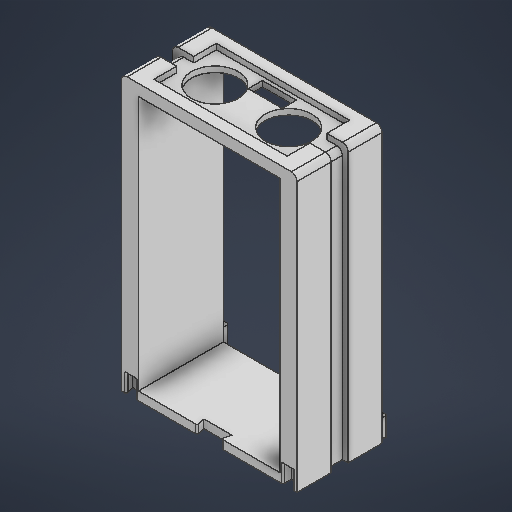
# Autodesk Inventor part: Car Sensor Gate
Saved by Autodesk Inventor 2026.4 (Build 304435000, 435)
## iProperties
Created: 2026-10-05
Part Number: Car Sensor Gate
Material: Generic
Document SubType Name: Modeling
Designer: LENOVO
Density: 1 g/cm^3
Appearance: Default
Author: LENOVO
Autodesk Inventor part; units mm, degrees
ref_plane "YZ Plane" through (0, 0, 0) normal (1, 0, 0) x (0, 1, 0)
ref_plane "XZ Plane" through (0, 0, 0) normal (0, 1, 0) x (-1, 0, 0)
ref_plane "XY Plane" through (0, 0, 0) normal (0, 0, 1) x (1, 0, 0)
sketch "Sketch1" plane through (0, 0, 0) normal (0, 1, 0) x (-1, 0, 0)
  line L0 (-25, 15) -> (25, 15)
  line L1 (25, 15) -> (25, -15)
  line L2 (25, -15) -> (-25, -15)
  line L3 (-25, -15) -> (-25, 15)
  line L4 (-25, 15) -> (25, -15) construction
  line L5 (25, 15) -> (-25, -15) construction
  point P0 (0, 0)
  dimension "d0" = 50
  dimension "d1" = 30
  constraints: 12 end point, 2 midpoint, 2 parallel, 1 horizontal, 1 perpendicular
  measures "d0" distance of L1.end L2.end
  measures "d1" distance of L0.end L1.end
extrude "Extrusion1" add sketch "Sketch1" along normal blind 2
sketch "Sketch2" plane through (0, 0, 0) normal (0, -1, 0) x (1, 0, 0)
  line L0 (25, 15) -> (25, -15) projected
  line L1 (25, 15) -> (31, 15)
  line L2 (31, 15) -> (31, -15)
  line L3 (31, -15) -> (25, -15)
  line L4 (25, -15) -> (25, 15)
  point P0 (0, 0)
  dimension "d4" = 6
  constraints: 8 end point, 2 parallel, 1 horizontal, 1 perpendicular
  measures "d4" distance of L2.end L3.end
extrude "Extrusion2" add sketch "Sketch2" against normal blind 6
mirror "Mirror1" about plane through (0, 0, 0) normal (1, 0, 0) of "Extrusion2"
sketch "Sketch3" plane through (0, 0, 0) normal (0, -1, 0) x (1, 0, 0)
  line L0 (-31, -15) -> (31, -15)
  line L1 (25, -15) -> (-25, -15)
  line L2 (-5, -12) -> (-5, -18)
  line L3 (-5, -18) -> (5, -18)
  line L4 (5, -18) -> (5, -12)
  line L5 (5, -12) -> (-5, -12)
  line L6 (-5, -12) -> (5, -18) construction
  line L7 (-5, -18) -> (5, -12) construction
  line L8 (-31, -15) -> (-25, -15)
  line L9 (-30, -12) -> (-30, -18)
  line L10 (-30, -18) -> (-26, -18)
  line L11 (-26, -18) -> (-26, -12)
  line L12 (-26, -12) -> (-30, -12)
  line L13 (-30, -12) -> (-26, -18) construction
  line L14 (-30, -18) -> (-26, -12) construction
  line L15 (-5, -18) -> (-4.1962, -15)
  line L16 (-5, -18) -> (-5, -14.8942) construction
  line L17 (5, -18) -> (4.1962, -15)
  line L18 (-30, -18) -> (-29.1962, -15)
  line L19 (-31, -15) -> (31, -15)
  line L20 (-30, -18) -> (-30, -14.8942) construction
  line L21 (26, -18) -> (26, -12)
  line L22 (30, -12) -> (30, -18)
  line L23 (30, -18) -> (26, -18)
  line L24 (26, -12) -> (30, -12)
  line L25 (30, -12) -> (26, -18) construction
  line L26 (30, -18) -> (29.1962, -15)
  line L27 (30, -18) -> (30, -14.8942) construction
  line L28 (31, -15) -> (25, -15)
  line L29 (30, -18) -> (26, -12) construction
  line L30 (31, -15) -> (-31, -15) projected
  line L31 (31, -15) -> (31, 15) projected
  line L32 (-31, 15) -> (31, 15) projected
  line L33 (-31, -15) -> (-31, 15) projected
  line L34 (-31, 0) -> (31, 0)
  line L35 (-31, 15) -> (31, 15)
  line L36 (25, 15) -> (-25, 15)
  line L37 (-5, 12) -> (-5, 18)
  line L38 (-5, 18) -> (5, 18)
  line L39 (5, 18) -> (5, 12)
  line L40 (5, 12) -> (-5, 12)
  line L41 (-5, 12) -> (5, 18) construction
  line L42 (-5, 18) -> (5, 12) construction
  line L43 (-31, 15) -> (-25, 15)
  line L44 (-30, 12) -> (-30, 18)
  line L45 (-30, 18) -> (-26, 18)
  line L46 (-26, 18) -> (-26, 12)
  line L47 (-26, 12) -> (-30, 12)
  line L48 (-30, 12) -> (-26, 18) construction
  line L49 (-30, 18) -> (-26, 12) construction
  line L50 (-5, 18) -> (-4.1962, 15)
  line L51 (-5, 18) -> (-5, 14.8942) construction
  line L52 (5, 18) -> (4.1962, 15)
  line L53 (-30, 18) -> (-29.1962, 15)
  line L54 (-31, 15) -> (31, 15)
  line L55 (-30, 18) -> (-30, 14.8942) construction
  line L56 (26, 18) -> (26, 12)
  line L57 (30, 12) -> (30, 18)
  line L58 (30, 18) -> (26, 18)
  line L59 (26, 12) -> (30, 12)
  line L60 (30, 12) -> (26, 18) construction
  line L61 (30, 18) -> (29.1962, 15)
  line L62 (30, 18) -> (30, 14.8942) construction
  line L63 (31, 15) -> (25, 15)
  line L64 (30, 18) -> (26, 12) construction
  line L65 (31, 15) -> (-31, 15)
  line L66 (-26, 12) -> (-26, 18)
  line L67 (-30, 18) -> (-30, 12)
  line L68 (-30, 18) -> (-26, 12) construction
  line L69 (-30, 12) -> (-26, 18) construction
  line L70 (-30, 12) -> (-30, 15.1058) construction
  line L71 (-30, 12) -> (-29.1962, 15)
  line L72 (-30, 12) -> (-26, 12)
  line L73 (5, 12) -> (5, 18)
  line L74 (5, 12) -> (4.1962, 15)
  line L75 (26, 12) -> (26, 18)
  line L76 (30, 12) -> (26, 12)
  line L77 (30, 12) -> (29.1962, 15)
  line L78 (30, 12) -> (26, 18) construction
  line L79 (30, 12) -> (30, 15.1058) construction
  line L80 (30, 18) -> (30, 12)
  line L81 (30, 18) -> (26, 12) construction
  line L82 (-5, 18) -> (-5, 12)
  line L83 (-5, 12) -> (-5, 15.1058) construction
  line L84 (-5, 12) -> (-4.1962, 15)
  line L85 (-5, 12) -> (5, 18) construction
  line L86 (-5, 18) -> (5, 12) construction
  line L87 (-5, 12) -> (5, 12)
  point P0 (0, 0)
  point P1 (-28, -15)
  point P2 (28, -15)
  point P3 (-131.328, -107.9645)
  point P4 (-131.328, -104.7683)
  point P5 (-131.328, -82.9645)
  point P6 (-131.328, -74.5722)
  point P7 (-131.328, -52.7683)
  point P8 (-131.328, -49.5722)
  point P9 (-28, 15)
  point P10 (28, 15)
  point P11 (26, -15)
  point P12 (-26, -15)
  dimension "d7" = 6
  dimension "d8" = 10
  dimension "d9" = 6
  dimension "d10" = 4
  dimension "d11" = 15
  dimension "d12" = 15
  constraints: 168 end point, 42 symmetric about line, 5 midpoint, 4 parallel, 4 point on line, 2 equal length, 2 perpendicular, 1 collinear
  measures "d7" distance of L4.end L3.end
  measures "d8" distance of L3.end L2.end
  measures "d9" distance of L11.end L10.end
  measures "d10" distance of L10.end L9.end
  measures "d11" angle of L15 L16
  measures "d12" angle of L18 L20
extrude "Extrusion3" add sketch "Sketch3" against normal blind 2 contours L0 L17 L3 L15 | L11 L10 L18 L0 | L0 L26 L23 L21
sketch "Sketch5" plane through (0, 0, 0) normal (0, -1, 0) x (1, 0, 0)
  line L0 (31, -15) -> (29.1962, -15) projected
  line L1 (31, -15) -> (31, 15) projected
  line L2 (-31, 15) -> (31, 15) projected
  line L3 (-31, -15) -> (-31, 15) projected
  line L4 (-29.1962, -15) -> (-31, -15) projected
  line L5 (-29.1962, -15) -> (-30, -18) projected
  line L6 (-30, -18) -> (-26, -18) projected
  line L7 (-26, -18) -> (-26, -15) projected
  line L8 (-4.1962, -15) -> (-26, -15) projected
  line L9 (-4.1962, -15) -> (-5, -18) projected
  line L10 (-5, -18) -> (5, -18) projected
  line L11 (5, -18) -> (4.1962, -15) projected
  line L12 (26, -15) -> (4.1962, -15) projected
  line L13 (26, -15) -> (26, -18) projected
  line L14 (26, -18) -> (30, -18) projected
  line L15 (30, -18) -> (29.1962, -15) projected
  line L16 (31, -15) -> (-31, -15)
  line L17 (-26, -15) -> (-29.1962, -15) projected
  line L18 (31, 0) -> (-31, 0)
  line L19 (-29.1962, -15) -> (-30, -12)
  line L20 (-30, -12) -> (-26, -12)
  line L21 (-26, -12) -> (-26, -15)
  line L22 (-4.1962, -15) -> (-5, -12)
  line L23 (-5, -12) -> (5, -12)
  line L24 (5, -12) -> (4.1962, -15)
  line L25 (26, -15) -> (26, -12)
  line L26 (26, -12) -> (30, -12)
  line L27 (30, -12) -> (29.1962, -15)
  line L28 (31, 15) -> (29.1962, 15)
  line L29 (31, 15) -> (31, -15)
  line L30 (-31, 15) -> (-31, -15)
  line L31 (-29.1962, 15) -> (-31, 15)
  line L32 (-29.1962, 15) -> (-30, 18)
  line L33 (-30, 18) -> (-26, 18)
  line L34 (-26, 18) -> (-26, 15)
  line L35 (-4.1962, 15) -> (-26, 15)
  line L36 (-4.1962, 15) -> (-5, 18)
  line L37 (-5, 18) -> (5, 18)
  line L38 (5, 18) -> (4.1962, 15)
  line L39 (26, 15) -> (4.1962, 15)
  line L40 (26, 15) -> (26, 18)
  line L41 (26, 18) -> (30, 18)
  line L42 (30, 18) -> (29.1962, 15)
  line L43 (31, 15) -> (-31, 15)
  line L44 (-26, 15) -> (-29.1962, 15)
  line L45 (-4.1962, 15) -> (-5, 12)
  line L46 (-26, 12) -> (-26, 15)
  line L47 (-29.1962, 15) -> (-30, 12)
  line L48 (-30, 12) -> (-26, 12)
  line L49 (-5, 12) -> (5, 12)
  line L50 (26, 15) -> (26, 12)
  line L51 (30, 12) -> (29.1962, 15)
  line L52 (26, 12) -> (30, 12)
  line L53 (5, 12) -> (4.1962, 15)
  point P0 (0, 0)
  constraints: 74 end point, 28 symmetric about line, 2 midpoint, 1 collinear
extrude "Extrusion4" cut sketch "Sketch5" against normal blind 2 contours L51 L52 L50 L2 | L2 L46 L48 L47 | L53 L49 L45 L2
fillet "Fillet1" radius 0.5 12 edges at (30, 1, -18) (26, 1, -18) (5, 1, -18) (-5, 1, -18) (-26, 1, -18) (-30, 1, -18) (-26, 1, 15) (-29.1962, 1, 15) (-4.1962, 1, 15) (26, 1, 15) (29.1962, 1, 15) (4.1962, 1, 15)
sketch "Sketch6" plane through (25, 6, 15) normal (0, 0, 1) x (1, 0, 0)
  line L0 (0, -4) -> (0, 0) projected
  line L1 (0, -4) -> (-50, -4)
  line L2 (-50, -4) -> (-50, 86)
  line L3 (-50, 86) -> (0, 86)
  line L4 (0, 86) -> (0, -4)
  line L5 (-56, 0) -> (-50, 0) projected
  line L6 (-56, 0) -> (6, 0)
  line L7 (6, 0) -> (6, 90)
  line L8 (6, 90) -> (-56, 90)
  line L9 (-56, 90) -> (-56, 0)
  point P0 (-25, -6)
  dimension "d24" = 90
  dimension "d25" = 62
  dimension "d26" = 90
  constraints: 16 end point, 4 parallel, 2 horizontal, 2 perpendicular
  measures "d24" distance of L1.end L2.end
  measures "d25" distance of L8.end L7.end
  measures "d26" distance of L7.end L6.end
extrude "Extrusion5" add sketch "Sketch6" against normal blind 30 contours L4 L3 L2 L5 L9 L8 L7 L6
sketch "Sketch7" plane through (-31, 96, 15) normal (0, 1, 0) x (1, 0, 0)
  line L0 (54.5, 26) -> (7.5, 26)
  line L1 (7.5, 26) -> (7.5, 4)
  line L2 (7.5, 4) -> (54.5, 4)
  line L3 (54.5, 4) -> (54.5, 26)
  line L4 (54.5, 26) -> (7.5, 4) construction
  line L5 (7.5, 26) -> (54.5, 4) construction
  circle A0 centre (44, 15) radius 8.25
  line L6 (31, 15) -> (31, 26)
  circle A1 centre (18, 15) radius 8.25
  line L7 (37, 24.75) -> (25, 24.75)
  line L8 (25, 24.75) -> (25, 19.75)
  line L9 (25, 19.75) -> (37, 19.75)
  line L10 (37, 19.75) -> (37, 24.75)
  line L11 (37, 24.75) -> (25, 19.75) construction
  line L12 (25, 24.75) -> (37, 19.75) construction
  point P0 (31, 22.25)
  dimension "d29" = 47
  dimension "d30" = 22
  dimension "d31" = 16.5
  dimension "d32" = 13
  dimension "d33" = 12
  dimension "d34" = 5
  dimension "d35" = 1.25
  constraints: 26 end point, 5 midpoint, 4 parallel, 2 centre point, 2 horizontal, 2 perpendicular, 1 point on line, 1 symmetric about line, 1 other
  measures "d29" distance of L2.end L1.end
  measures "d30" distance of L1.end L0.end
  measures "d31" diameter of A0
  measures "d32" distance of A0.centre L6.start
  measures "d33" distance of L9.end L8.end
  measures "d34" distance of L8.end L7.end
  measures "d35" distance between parallel lines of L0 L7
extrude "Extrusion6" cut sketch "Sketch7" against normal blind 4 contours A0 | L9 L8 L7 L6 | L6 L7 L10 L9 | A1
sketch "Sketch8" plane through (-31, 96, 15) normal (0, 1, 0) x (1, 0, 0)
  line L0 (54.5, 26) -> (7.5, 26)
  line L1 (7.5, 26) -> (7.5, 4)
  line L2 (7.5, 4) -> (54.5, 4)
  line L3 (54.5, 4) -> (54.5, 26)
  line L4 (54.5, 26) -> (7.5, 4) construction
  line L5 (7.5, 26) -> (54.5, 4) construction
  point P0 (31, 15)
  dimension "d38" = 47
  dimension "d39" = 22
  constraints: 12 end point, 2 midpoint, 2 parallel, 1 horizontal, 1 perpendicular
  measures "d38" distance of L2.end L1.end
  measures "d39" distance of L1.end L0.end
extrude "Extrusion7" cut sketch "Sketch8" against normal blind 2
sketch "Sketch9" plane through (-31, 0, -15) normal (-1, 0, 0) x (0, 0, 1)
  line L0 (0, 0) -> (30, 0) projected
  line L1 (30, 0) -> (30, 96) projected
  line L2 (30, 96) -> (0, 96) projected
  line L3 (0, 0) -> (0, 96) projected
  line L4 (15, 0) -> (12, 0)
  line L5 (12, 0) -> (12, 96)
  line L6 (12, 96) -> (18, 96)
  line L7 (18, 96) -> (18, 0)
  line L8 (18, 0) -> (12, 0)
  line L9 (12, 0) -> (12, 96)
  dimension "d42" = 3
  dimension "d43" = 6
  constraints: 12 end point, 3 point on line, 2 parallel, 2 perpendicular, 1 horizontal
  measures "d42" distance of L4.start L4.end
  measures "d43" distance of L7.end L8.end
extrude "Extrusion8" cut sketch "Sketch9" against normal blind 2 contours L5 L2 L7 L0
sketch "Sketch10" plane through (-31, 96, 15) normal (0, 1, 0) x (1, 0, 0)
  line L0 (7.5, 4) -> (7.5, 26) projected
  line L1 (0, 18) -> (2, 18) projected
  line L2 (0, 18) -> (7.5, 18)
  line L3 (7.5, 18) -> (7.5, 12)
  line L4 (7.5, 12) -> (0, 12)
  line L5 (0, 12) -> (0, 18)
  point P0 (31, 15)
  dimension "d46" = 6
  constraints: 8 end point, 2 parallel, 1 horizontal, 1 perpendicular, 1 point on line
  measures "d46" distance of L2.end L3.end
extrude "Extrusion9" cut sketch "Sketch10" against normal blind 2
fillet "Fillet2" radius 2 1 edges at (-29, 94, 0)
mirror "Mirror2" about plane through (0, 0, 0) normal (1, 0, 0) of "Extrusion8", "Extrusion9", "Fillet2"
sketch "Sketch11" plane through (0, 2, 0) normal (0, -1, 0) x (1, 0, 0)
  line L0 (-29.8478, 15) -> (-25.5, 15) projected
  arc A0 (-29.3648, 14.3706) -> (-29.8478, 15) centre (-29.8478, 14.5) ccw projected
  line L1 (-30, 12) -> (-29.3648, 14.3706) projected
  line L2 (-26, 12) -> (-30, 12) projected
  line L3 (-26, 14.5) -> (-26, 12) projected
  arc A1 (-25.5, 15) -> (-26, 14.5) centre (-25.5, 14.5) ccw projected
  line L4 (25.5, 15) -> (29.8478, 15) projected
  arc A2 (26, 14.5) -> (25.5, 15) centre (25.5, 14.5) ccw projected
  line L5 (26, 12) -> (26, 14.5) projected
  line L6 (30, 12) -> (26, 12) projected
  line L7 (29.3648, 14.3706) -> (30, 12) projected
  arc A3 (29.8478, 15) -> (29.3648, 14.3706) centre (29.8478, 14.5) ccw projected
  point P0 (0, 0)
extrude "Extrusion10" cut sketch "Sketch11" against normal blind 3.5
sketch "Sketch12" plane through (0, 2, 0) normal (0, 1, 0) x (1, 0, 0)
  arc A0 (26.5, 18) -> (26, 17.5) centre (26.5, 17.5) ccw projected
  line L0 (26, 17.5) -> (26, 15) projected
  line L1 (29.1962, 15) -> (26, 15) projected
  line L2 (29.1962, 15) -> (29.8314, 17.3706) projected
  arc A1 (29.8314, 17.3706) -> (29.3484, 18) centre (29.3484, 17.5) ccw projected
  line L3 (29.3484, 18) -> (26.5, 18) projected
  arc A2 (-29.3484, 18) -> (-29.8314, 17.3706) centre (-29.3484, 17.5) ccw projected
  line L4 (-29.8314, 17.3706) -> (-29.1962, 15) projected
  line L5 (-26, 15) -> (-29.1962, 15) projected
  line L6 (-26, 15) -> (-26, 17.5) projected
  arc A3 (-26, 17.5) -> (-26.5, 18) centre (-26.5, 17.5) ccw projected
  line L7 (-26.5, 18) -> (-29.3484, 18) projected
  point P0 (0, 0)
extrude "Extrusion11" add sketch "Sketch12" along normal blind 3.5
sketch "Sketch13" plane through (0, 0, 0) normal (0, -1, 0) x (1, 0, 0)
  line L0 (29, 3) -> (31, 3) projected
  line L1 (31, 3) -> (31, 15) projected
  line L2 (29.8478, 15) -> (31, 15) projected
  arc A0 (29.8478, 15) -> (29.3648, 14.3706) centre (29.8478, 14.5) ccw projected
  line L3 (29.3648, 14.3706) -> (30, 12) projected
  line L4 (30, 12) -> (26, 12) projected
  line L5 (26, 12) -> (26, 14.5) projected
  arc A1 (26, 14.5) -> (25.5, 15) centre (25.5, 14.5) ccw projected
  line L6 (4.8478, 15) -> (25.5, 15) projected
  arc A2 (4.8478, 15) -> (4.3648, 14.3706) centre (4.8478, 14.5) ccw projected
  line L7 (4.3648, 14.3706) -> (5, 12) projected
  line L8 (5, 12) -> (-5, 12) projected
  line L9 (-5, 12) -> (-4.3648, 14.3706) projected
  arc A3 (-4.3648, 14.3706) -> (-4.8478, 15) centre (-4.8478, 14.5) ccw projected
  line L10 (-25.5, 15) -> (-4.8478, 15) projected
  arc A4 (-25.5, 15) -> (-26, 14.5) centre (-25.5, 14.5) ccw projected
  line L11 (-26, 14.5) -> (-26, 12) projected
  line L12 (-26, 12) -> (-30, 12) projected
  line L13 (-30, 12) -> (-29.3648, 14.3706) projected
  arc A5 (-29.3648, 14.3706) -> (-29.8478, 15) centre (-29.8478, 14.5) ccw projected
  line L14 (-31, 15) -> (-29.8478, 15) projected
  line L15 (-31, 3) -> (-31, 15) projected
  line L16 (-31, 3) -> (-29, 3) projected
  line L17 (-29, 3) -> (-29, -3) projected
  line L18 (-29, -3) -> (-31, -3) projected
  line L19 (-31, -15) -> (-31, -3) projected
  line L20 (-29.1962, -15) -> (-31, -15) projected
  line L21 (-29.1962, -15) -> (-29.8314, -17.3706) projected
  arc A6 (-29.8314, -17.3706) -> (-29.3484, -18) centre (-29.3484, -17.5) ccw projected
  line L22 (-29.3484, -18) -> (-26.5, -18) projected
  arc A7 (-26.5, -18) -> (-26, -17.5) centre (-26.5, -17.5) ccw projected
  line L23 (-26, -17.5) -> (-26, -15) projected
  line L24 (-4.1962, -15) -> (-26, -15) projected
  line L25 (-4.1962, -15) -> (-4.8314, -17.3706) projected
  arc A8 (-4.8314, -17.3706) -> (-4.3484, -18) centre (-4.3484, -17.5) ccw projected
  line L26 (-4.3484, -18) -> (4.3484, -18) projected
  arc A9 (4.3484, -18) -> (4.8314, -17.3706) centre (4.3484, -17.5) ccw projected
  line L27 (4.8314, -17.3706) -> (4.1962, -15) projected
  line L28 (26, -15) -> (4.1962, -15) projected
  line L29 (26, -15) -> (26, -17.5) projected
  arc A10 (26, -17.5) -> (26.5, -18) centre (26.5, -17.5) ccw projected
  line L30 (26.5, -18) -> (29.3484, -18) projected
  arc A11 (29.3484, -18) -> (29.8314, -17.3706) centre (29.3484, -17.5) ccw projected
  line L31 (29.8314, -17.3706) -> (29.1962, -15) projected
  line L32 (31, -15) -> (29.1962, -15) projected
  line L33 (31, -15) -> (31, -3) projected
  line L34 (31, -3) -> (29, -3) projected
  line L35 (29, -3) -> (29, 3) projected
  point P0 (0, 0)
extrude "Extrusion12" add sketch "Sketch13" along normal blind 1
fillet "Fillet3" radius 2 4 edges at (31, 96, -9) (31, 96, 9) (-31, 96, 9) (-31, 96, -9)
body "Solid1"
